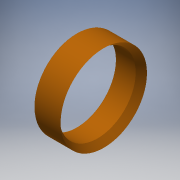
# Autodesk Inventor part: 15-0012-0308
Saved by Autodesk Inventor 2016 SP2 (Build 200236200, 236)
## iProperties
Created: 2017-10-23
Part Number: 15-0012-0308
Material: Plastic (PEEK)
Document SubType Name: Modeling
Designer: jellerm1
Density: 1.32 g/cm^3
Appearance: Orange
User Status: Work in Progress
Description: Spacer-3
RuleStatus: InUse
Category: -
Company: Universiteit van Amsterdam
BeforeDocSave0: Open Form
Author: jellerm1
Revision Number: A
Autodesk Inventor part; units mm, degrees
ref_plane "YZ Plane" through (0, 0, 0) normal (1, 0, 0) x (0, 1, 0)
ref_plane "XZ Plane" through (0, 0, 0) normal (0, 1, 0) x (-1, 0, 0)
ref_plane "XY Plane" through (0, 0, 0) normal (0, 0, 1) x (1, 0, 0)
sketch "Sketch1" plane through (0, 0, 0) normal (0, 0, 1) x (1, 0, 0)
  line L0 (0, 167.048) -> (0, -167.048) construction
  line L1 (-49.8592, 0) -> (284.2368, 0) construction
  line L2 (0, 22.5) -> (12.8186, 22.5)
  line L3 (12.8186, 22.5) -> (16.5477, 25.4)
  line L4 (16.5477, 25.4) -> (0.5942, 25.4)
  line L5 (0.5942, 25.4) -> (0, 22.5) construction
  line L6 (0, 0) -> (27.5804, 0)
  circle A0 centre (33.3088, 0) radius 30.34 construction
  line L7 (22.7161, 23.95) -> (14.6831, 23.95) construction
  line L8 (19.1655, 23.95) -> (0.2971, 23.95) construction
  circle A1 centre (117.1888, 0) radius 119.32 construction
  arc A2 (1.7776, 25.4) -> (1.7776, 22.5) centre (1.7776, 23.95) ccw
  line L9 (1.7776, 23.95) -> (0.3578, 24.2446) construction
  dimension "d4" = 60.68
  dimension "d0" = 50.8
  dimension "d1" = 45
  dimension "d3" = 0
  dimension "d6" = 1.45
  dimension "d10" = 238.64
  dimension "d11" = 83.88
  dimension "d12" = 11.724
  constraints: 16 end point, 5 point on circle, 5 point on line, 3 midpoint, 3 tangent, 2 centre point, 1 horizontal, 1 parallel, 1 perpendicular, 4 other
  measures "d0" diameter of L4 L6
  measures "d1" diameter of L2 L6
  measures "d3" distance from line of L0 L2.start
  measures "d6" distance between parallel lines of L7 L2
  measures "d10" diameter of A1
  measures "d11" distance of A1.centre point (33.309, 0)
  measures "d12" angle of L8 L9
revolve "Revolution1" add sketch "Sketch1" angle 360 about axis through (0, 0, 0) along (1, 0, 0)
body "Solid1"
